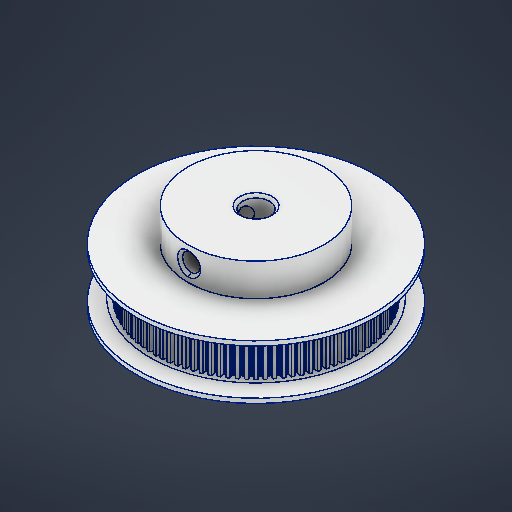
# Autodesk Inventor part: 48 Timing Belt Pulli
Saved by Autodesk Inventor 2026.2 (Build 302298010, 298A)
## iProperties
Created: 2026-04-25
Part Number: 48 Timing Belt Pulli
Material: 알루미늄 6061
Document SubType Name: Modeling
Designer: work
Density: 2.7 g/cm^3
Appearance: 알루미늄 - 평지
Author: work
Autodesk Inventor part; units mm, degrees
ref_plane "XZ Plane" through (0, 0, 0) normal (0, 1, 0) x (-1, 0, 0)
ref_plane "XY Plane" through (0, 0, 0) normal (0, 0, 1) x (1, 0, 0)
sketch "스케치1" plane through (0, 0, 0) normal (0, 1, 0) x (-1, 0, 0)
  circle A0 centre (0, 0) radius 22
  dimension "d0" = 44
  constraints: 1 centre point, 1 coincident
  measures "d0" diameter of A0
extrude "돌출1" add sketch "스케치1" along normal blind 10
sketch "스케치2" plane through (0, 10, 0) normal (0, 1, 0) x (1, 0, 0)
  circle A0 centre (0, 0) radius 12.5
  dimension "d3" = 25
  constraints: 1 centre point, 1 coincident
  measures "d3" diameter of A0
extrude "돌출2" add sketch "스케치2" along normal blind 6
sketch "스케치3" plane through (0, 16, 0) normal (0, 1, 0) x (1, 0, 0)
  circle A0 centre (0, 0) radius 2.5
  dimension "d6" = 5
  constraints: 1 centre point, 1 coincident
  measures "d6" diameter of A0
extrude "돌출3" cut sketch "스케치3" against normal through all
ref_plane "작업 평면1" through (0, 1.5, 0) normal (0, -1, 0) x (1, 0, 0)
sketch "스케치4" plane through (0, 1.5, 0) normal (0, -1, 0) x (1, 0, 0)
  circle A0 centre (0, 0) radius 2.5 projected
  line L0 (0, 0) -> (0, 18.7) construction
  line L1 (0, 18.7) -> (0.2511, 18.7)
  line L2 (0.2511, 18.7) -> (0.3833, 17.95)
  line L3 (0.3833, 17.95) -> (0.6344, 17.95)
  line L4 (0, 18.7) -> (-0.2511, 18.7)
  line L5 (-0.2511, 18.7) -> (-0.3833, 17.95)
  line L6 (-0.3833, 17.95) -> (-0.6344, 17.95)
  circle A1 centre (0, 0) radius 2.5 projected
  circle A2 centre (0, 0) radius 22 projected
  line L7 (0, 0) -> (-1.223, 18.66) construction
  line L8 (-1.223, 18.66) -> (-0.9725, 18.6764)
  line L9 (-0.9725, 18.6764) -> (-0.7915, 17.9366)
  line L10 (-0.7915, 17.9366) -> (-0.541, 17.9531)
  line L11 (-1.223, 18.66) -> (-1.4736, 18.6435)
  line L12 (-1.4736, 18.6435) -> (-1.5565, 17.8865)
  line L13 (-1.5565, 17.8865) -> (-1.807, 17.8701)
  line L14 (0, 0) -> (-2.4408, 18.54) construction
  line L15 (-2.4408, 18.54) -> (-2.1919, 18.5728)
  line L16 (-2.1919, 18.5728) -> (-1.9629, 17.8465)
  line L17 (-1.9629, 17.8465) -> (-1.714, 17.8792)
  line L18 (-2.4408, 18.54) -> (-2.6898, 18.5072)
  line L19 (-2.6898, 18.5072) -> (-2.723, 17.7464)
  line L20 (-2.723, 17.7464) -> (-2.9719, 17.7136)
  line L21 (0, 0) -> (-3.6482, 18.3407) construction
  line L22 (-3.6482, 18.3407) -> (-3.4019, 18.3897)
  line L23 (-3.4019, 18.3897) -> (-3.1259, 17.6799)
  line L24 (-3.1259, 17.6799) -> (-2.8797, 17.7289)
  line L25 (-3.6482, 18.3407) -> (-3.8944, 18.2917)
  line L26 (-3.8944, 18.2917) -> (-3.8778, 17.5303)
  line L27 (-3.8778, 17.5303) -> (-4.1241, 17.4813)
  line L28 (0, 0) -> (-4.8399, 18.0628) construction
  line L29 (-4.8399, 18.0628) -> (-4.5974, 18.1278)
  line L30 (-4.5974, 18.1278) -> (-4.2756, 17.4376)
  line L31 (-4.2756, 17.4376) -> (-4.033, 17.5026)
  line L32 (-4.8399, 18.0628) -> (-5.0824, 17.9978)
  line L33 (-5.0824, 17.9978) -> (-5.0161, 17.2392)
  line L34 (-5.0161, 17.2392) -> (-5.2586, 17.1742)
  line L35 (0, 0) -> (-6.0109, 17.7076) construction
  line L36 (-6.0109, 17.7076) -> (-5.7732, 17.7883)
  line L37 (-5.7732, 17.7883) -> (-5.4069, 17.1206)
  line L38 (-5.4069, 17.1206) -> (-5.1691, 17.2013)
  line L39 (-6.0109, 17.7076) -> (-6.2487, 17.6269)
  line L40 (-6.2487, 17.6269) -> (-6.1328, 16.8742)
  line L41 (-6.1328, 16.8742) -> (-6.3705, 16.7935)
  line L42 (0, 0) -> (-7.1562, 17.2765) construction
  line L43 (-7.1562, 17.2765) -> (-6.9242, 17.3726)
  line L44 (-6.9242, 17.3726) -> (-6.515, 16.7303)
  line L45 (-6.515, 16.7303) -> (-6.2831, 16.8264)
  line L46 (-7.1562, 17.2765) -> (-7.3881, 17.1805)
  line L47 (-7.3881, 17.1805) -> (-7.2233, 16.437)
  line L48 (-7.2233, 16.437) -> (-7.4553, 16.3409)
  line L49 (0, 0) -> (-8.2708, 16.7715) construction
  line L50 (-8.2708, 16.7715) -> (-8.0456, 16.8826)
  line L51 (-8.0456, 16.8826) -> (-7.5953, 16.2684)
  line L52 (-7.5953, 16.2684) -> (-7.3701, 16.3794)
  line L53 (-8.2708, 16.7715) -> (-8.496, 16.6605)
  line L54 (-8.496, 16.6605) -> (-8.2829, 15.9293)
  line L55 (-8.2829, 15.9293) -> (-8.508, 15.8183)
  line L56 (0, 0) -> (-9.35, 16.1947) construction
  line L57 (-9.35, 16.1947) -> (-9.1326, 16.3202)
  line L58 (-9.1326, 16.3202) -> (-8.643, 15.7368)
  line L59 (-8.643, 15.7368) -> (-8.4256, 15.8623)
  line L60 (-9.35, 16.1947) -> (-9.5674, 16.0691)
  line L61 (-9.5674, 16.0691) -> (-9.307, 15.3535)
  line L62 (-9.307, 15.3535) -> (-9.5244, 15.228)
  line L63 (0, 0) -> (-10.3892, 15.5485) construction
  line L64 (-10.3892, 15.5485) -> (-10.1804, 15.688)
  line L65 (-10.1804, 15.688) -> (-9.6538, 15.1378)
  line L66 (-9.6538, 15.1378) -> (-9.445, 15.2773)
  line L67 (-10.3892, 15.5485) -> (-10.5979, 15.409)
  line L68 (-10.5979, 15.409) -> (-10.2912, 14.7119)
  line L69 (-10.2912, 14.7119) -> (-10.4999, 14.5724)
  line L70 (0, 0) -> (-11.3838, 14.8357) construction
  line L71 (-11.3838, 14.8357) -> (-11.1847, 14.9885)
  line L72 (-11.1847, 14.9885) -> (-10.6232, 14.474)
  line L73 (-10.6232, 14.474) -> (-10.424, 14.6269)
  line L74 (-11.3838, 14.8357) -> (-11.583, 14.6829)
  line L75 (-11.583, 14.6829) -> (-11.2314, 14.0073)
  line L76 (-11.2314, 14.0073) -> (-11.4306, 13.8545)
  line L77 (0, 0) -> (-12.3298, 14.0594) construction
  line L78 (-12.3298, 14.0594) -> (-12.141, 14.2249)
  line L79 (-12.141, 14.2249) -> (-11.5471, 13.7483)
  line L80 (-11.5471, 13.7483) -> (-11.3583, 13.9138)
  line L81 (-12.3298, 14.0594) -> (-12.5185, 13.8939)
  line L82 (-12.5185, 13.8939) -> (-12.1234, 13.2428)
  line L83 (-12.1234, 13.2428) -> (-12.3122, 13.0773)
  line L84 (0, 0) -> (-13.2229, 13.2229) construction
  line L85 (-13.2229, 13.2229) -> (-13.0454, 13.4004)
  line L86 (-13.0454, 13.4004) -> (-12.4215, 12.9636)
  line L87 (-12.4215, 12.9636) -> (-12.244, 13.1411)
  line L88 (-13.2229, 13.2229) -> (-13.4004, 13.0454)
  line L89 (-13.4004, 13.0454) -> (-12.9636, 12.4215)
  line L90 (-12.9636, 12.4215) -> (-13.1411, 12.244)
  line L91 (0, 0) -> (-14.0594, 12.3298) construction
  line L92 (-14.0594, 12.3298) -> (-13.8939, 12.5185)
  line L93 (-13.8939, 12.5185) -> (-13.2428, 12.1234)
  line L94 (-13.2428, 12.1234) -> (-13.0773, 12.3122)
  line L95 (-14.0594, 12.3298) -> (-14.2249, 12.141)
  line L96 (-14.2249, 12.141) -> (-13.7483, 11.5471)
  line L97 (-13.7483, 11.5471) -> (-13.9138, 11.3583)
  line L98 (0, 0) -> (-14.8357, 11.3838) construction
  line L99 (-14.8357, 11.3838) -> (-14.6829, 11.583)
  line L100 (-14.6829, 11.583) -> (-14.0073, 11.2314)
  line L101 (-14.0073, 11.2314) -> (-13.8545, 11.4306)
  line L102 (-14.8357, 11.3838) -> (-14.9885, 11.1847)
  line L103 (-14.9885, 11.1847) -> (-14.474, 10.6232)
  line L104 (-14.474, 10.6232) -> (-14.6269, 10.424)
  line L105 (0, 0) -> (-15.5485, 10.3892) construction
  line L106 (-15.5485, 10.3892) -> (-15.409, 10.5979)
  line L107 (-15.409, 10.5979) -> (-14.7119, 10.2912)
  line L108 (-14.7119, 10.2912) -> (-14.5724, 10.4999)
  line L109 (-15.5485, 10.3892) -> (-15.688, 10.1804)
  line L110 (-15.688, 10.1804) -> (-15.1378, 9.6538)
  line L111 (-15.1378, 9.6538) -> (-15.2773, 9.445)
  line L112 (0, 0) -> (-16.1947, 9.35) construction
  line L113 (-16.1947, 9.35) -> (-16.0691, 9.5674)
  line L114 (-16.0691, 9.5674) -> (-15.3535, 9.307)
  line L115 (-15.3535, 9.307) -> (-15.228, 9.5244)
  line L116 (-16.1947, 9.35) -> (-16.3202, 9.1326)
  line L117 (-16.3202, 9.1326) -> (-15.7368, 8.643)
  line L118 (-15.7368, 8.643) -> (-15.8623, 8.4256)
  line L119 (0, 0) -> (-16.7715, 8.2708) construction
  line L120 (-16.7715, 8.2708) -> (-16.6605, 8.496)
  line L121 (-16.6605, 8.496) -> (-15.9293, 8.2829)
  line L122 (-15.9293, 8.2829) -> (-15.8183, 8.508)
  line L123 (-16.7715, 8.2708) -> (-16.8826, 8.0456)
  line L124 (-16.8826, 8.0456) -> (-16.2684, 7.5953)
  line L125 (-16.2684, 7.5953) -> (-16.3794, 7.3701)
  line L126 (0, 0) -> (-17.2765, 7.1562) construction
  line L127 (-17.2765, 7.1562) -> (-17.1805, 7.3881)
  line L128 (-17.1805, 7.3881) -> (-16.437, 7.2233)
  line L129 (-16.437, 7.2233) -> (-16.3409, 7.4553)
  line L130 (-17.2765, 7.1562) -> (-17.3726, 6.9242)
  line L131 (-17.3726, 6.9242) -> (-16.7303, 6.515)
  line L132 (-16.7303, 6.515) -> (-16.8264, 6.2831)
  line L133 (0, 0) -> (-17.7076, 6.0109) construction
  line L134 (-17.7076, 6.0109) -> (-17.6269, 6.2487)
  line L135 (-17.6269, 6.2487) -> (-16.8742, 6.1328)
  line L136 (-16.8742, 6.1328) -> (-16.7935, 6.3705)
  line L137 (-17.7076, 6.0109) -> (-17.7883, 5.7732)
  line L138 (-17.7883, 5.7732) -> (-17.1206, 5.4069)
  line L139 (-17.1206, 5.4069) -> (-17.2013, 5.1691)
  line L140 (0, 0) -> (-18.0628, 4.8399) construction
  line L141 (-18.0628, 4.8399) -> (-17.9978, 5.0824)
  line L142 (-17.9978, 5.0824) -> (-17.2392, 5.0161)
  line L143 (-17.2392, 5.0161) -> (-17.1742, 5.2586)
  line L144 (-18.0628, 4.8399) -> (-18.1278, 4.5974)
  line L145 (-18.1278, 4.5974) -> (-17.4376, 4.2756)
  line L146 (-17.4376, 4.2756) -> (-17.5026, 4.033)
  line L147 (0, 0) -> (-18.3407, 3.6482) construction
  line L148 (-18.3407, 3.6482) -> (-18.2917, 3.8944)
  line L149 (-18.2917, 3.8944) -> (-17.5303, 3.8778)
  line L150 (-17.5303, 3.8778) -> (-17.4813, 4.1241)
  line L151 (-18.3407, 3.6482) -> (-18.3897, 3.4019)
  line L152 (-18.3897, 3.4019) -> (-17.6799, 3.1259)
  line L153 (-17.6799, 3.1259) -> (-17.7289, 2.8797)
  line L154 (0, 0) -> (-18.54, 2.4408) construction
  line L155 (-18.54, 2.4408) -> (-18.5072, 2.6898)
  line L156 (-18.5072, 2.6898) -> (-17.7464, 2.723)
  line L157 (-17.7464, 2.723) -> (-17.7136, 2.9719)
  line L158 (-18.54, 2.4408) -> (-18.5728, 2.1919)
  line L159 (-18.5728, 2.1919) -> (-17.8465, 1.9629)
  line L160 (-17.8465, 1.9629) -> (-17.8792, 1.714)
  line L161 (0, 0) -> (-18.66, 1.223) construction
  line L162 (-18.66, 1.223) -> (-18.6435, 1.4736)
  line L163 (-18.6435, 1.4736) -> (-17.8865, 1.5565)
  line L164 (-17.8865, 1.5565) -> (-17.8701, 1.807)
  line L165 (-18.66, 1.223) -> (-18.6764, 0.9725)
  line L166 (-18.6764, 0.9725) -> (-17.9366, 0.7915)
  line L167 (-17.9366, 0.7915) -> (-17.9531, 0.541)
  line L168 (0, 0) -> (-18.7, 0) construction
  line L169 (-18.7, 0) -> (-18.7, 0.2511)
  line L170 (-18.7, 0.2511) -> (-17.95, 0.3833)
  line L171 (-17.95, 0.3833) -> (-17.95, 0.6344)
  line L172 (-18.7, 0) -> (-18.7, -0.2511)
  line L173 (-18.7, -0.2511) -> (-17.95, -0.3833)
  line L174 (-17.95, -0.3833) -> (-17.95, -0.6344)
  line L175 (0, 0) -> (-18.66, -1.223) construction
  line L176 (-18.66, -1.223) -> (-18.6764, -0.9725)
  line L177 (-18.6764, -0.9725) -> (-17.9366, -0.7915)
  line L178 (-17.9366, -0.7915) -> (-17.9531, -0.541)
  line L179 (-18.66, -1.223) -> (-18.6435, -1.4736)
  line L180 (-18.6435, -1.4736) -> (-17.8865, -1.5565)
  line L181 (-17.8865, -1.5565) -> (-17.8701, -1.807)
  line L182 (0, 0) -> (-18.54, -2.4408) construction
  line L183 (-18.54, -2.4408) -> (-18.5728, -2.1919)
  line L184 (-18.5728, -2.1919) -> (-17.8465, -1.9629)
  line L185 (-17.8465, -1.9629) -> (-17.8792, -1.714)
  line L186 (-18.54, -2.4408) -> (-18.5072, -2.6898)
  line L187 (-18.5072, -2.6898) -> (-17.7464, -2.723)
  line L188 (-17.7464, -2.723) -> (-17.7136, -2.9719)
  line L189 (0, 0) -> (-18.3407, -3.6482) construction
  line L190 (-18.3407, -3.6482) -> (-18.3897, -3.4019)
  line L191 (-18.3897, -3.4019) -> (-17.6799, -3.1259)
  line L192 (-17.6799, -3.1259) -> (-17.7289, -2.8797)
  line L193 (-18.3407, -3.6482) -> (-18.2917, -3.8944)
  line L194 (-18.2917, -3.8944) -> (-17.5303, -3.8778)
  line L195 (-17.5303, -3.8778) -> (-17.4813, -4.1241)
  line L196 (0, 0) -> (-18.0628, -4.8399) construction
  line L197 (-18.0628, -4.8399) -> (-18.1278, -4.5974)
  line L198 (-18.1278, -4.5974) -> (-17.4376, -4.2756)
  line L199 (-17.4376, -4.2756) -> (-17.5026, -4.033)
  line L200 (-18.0628, -4.8399) -> (-17.9978, -5.0824)
  line L201 (-17.9978, -5.0824) -> (-17.2392, -5.0161)
  line L202 (-17.2392, -5.0161) -> (-17.1742, -5.2586)
  line L203 (0, 0) -> (-17.7076, -6.0109) construction
  line L204 (-17.7076, -6.0109) -> (-17.7883, -5.7732)
  line L205 (-17.7883, -5.7732) -> (-17.1206, -5.4069)
  line L206 (-17.1206, -5.4069) -> (-17.2013, -5.1691)
  line L207 (-17.7076, -6.0109) -> (-17.6269, -6.2487)
  line L208 (-17.6269, -6.2487) -> (-16.8742, -6.1328)
  line L209 (-16.8742, -6.1328) -> (-16.7935, -6.3705)
  line L210 (0, 0) -> (-17.2765, -7.1562) construction
  line L211 (-17.2765, -7.1562) -> (-17.3726, -6.9242)
  line L212 (-17.3726, -6.9242) -> (-16.7303, -6.515)
  line L213 (-16.7303, -6.515) -> (-16.8264, -6.2831)
  line L214 (-17.2765, -7.1562) -> (-17.1805, -7.3881)
  line L215 (-17.1805, -7.3881) -> (-16.437, -7.2233)
  line L216 (-16.437, -7.2233) -> (-16.3409, -7.4553)
  line L217 (0, 0) -> (-16.7715, -8.2708) construction
  line L218 (-16.7715, -8.2708) -> (-16.8826, -8.0456)
  line L219 (-16.8826, -8.0456) -> (-16.2684, -7.5953)
  line L220 (-16.2684, -7.5953) -> (-16.3794, -7.3701)
  line L221 (-16.7715, -8.2708) -> (-16.6605, -8.496)
  line L222 (-16.6605, -8.496) -> (-15.9293, -8.2829)
  line L223 (-15.9293, -8.2829) -> (-15.8183, -8.508)
  line L224 (0, 0) -> (-16.1947, -9.35) construction
  line L225 (-16.1947, -9.35) -> (-16.3202, -9.1326)
  line L226 (-16.3202, -9.1326) -> (-15.7368, -8.643)
  line L227 (-15.7368, -8.643) -> (-15.8623, -8.4256)
  line L228 (-16.1947, -9.35) -> (-16.0691, -9.5674)
  line L229 (-16.0691, -9.5674) -> (-15.3535, -9.307)
  line L230 (-15.3535, -9.307) -> (-15.228, -9.5244)
  line L231 (0, 0) -> (-15.5485, -10.3892) construction
  line L232 (-15.5485, -10.3892) -> (-15.688, -10.1804)
  line L233 (-15.688, -10.1804) -> (-15.1378, -9.6538)
  line L234 (-15.1378, -9.6538) -> (-15.2773, -9.445)
  line L235 (-15.5485, -10.3892) -> (-15.409, -10.5979)
  line L236 (-15.409, -10.5979) -> (-14.7119, -10.2912)
  line L237 (-14.7119, -10.2912) -> (-14.5724, -10.4999)
  line L238 (0, 0) -> (-14.8357, -11.3838) construction
  line L239 (-14.8357, -11.3838) -> (-14.9885, -11.1847)
  line L240 (-14.9885, -11.1847) -> (-14.474, -10.6232)
  line L241 (-14.474, -10.6232) -> (-14.6269, -10.424)
  line L242 (-14.8357, -11.3838) -> (-14.6829, -11.583)
  line L243 (-14.6829, -11.583) -> (-14.0073, -11.2314)
  line L244 (-14.0073, -11.2314) -> (-13.8545, -11.4306)
  line L245 (0, 0) -> (-14.0594, -12.3298) construction
  line L246 (-14.0594, -12.3298) -> (-14.2249, -12.141)
  line L247 (-14.2249, -12.141) -> (-13.7483, -11.5471)
  line L248 (-13.7483, -11.5471) -> (-13.9138, -11.3583)
  line L249 (-14.0594, -12.3298) -> (-13.8939, -12.5185)
  line L250 (-13.8939, -12.5185) -> (-13.2428, -12.1234)
  line L251 (-13.2428, -12.1234) -> (-13.0773, -12.3122)
  line L252 (0, 0) -> (-13.2229, -13.2229) construction
  line L253 (-13.2229, -13.2229) -> (-13.4004, -13.0454)
  line L254 (-13.4004, -13.0454) -> (-12.9636, -12.4215)
  line L255 (-12.9636, -12.4215) -> (-13.1411, -12.244)
  line L256 (-13.2229, -13.2229) -> (-13.0454, -13.4004)
  line L257 (-13.0454, -13.4004) -> (-12.4215, -12.9636)
  line L258 (-12.4215, -12.9636) -> (-12.244, -13.1411)
  line L259 (0, 0) -> (-12.3298, -14.0594) construction
  line L260 (-12.3298, -14.0594) -> (-12.5185, -13.8939)
  line L261 (-12.5185, -13.8939) -> (-12.1234, -13.2428)
  line L262 (-12.1234, -13.2428) -> (-12.3122, -13.0773)
  line L263 (-12.3298, -14.0594) -> (-12.141, -14.2249)
  line L264 (-12.141, -14.2249) -> (-11.5471, -13.7483)
  line L265 (-11.5471, -13.7483) -> (-11.3583, -13.9138)
  line L266 (0, 0) -> (-11.3838, -14.8357) construction
  line L267 (-11.3838, -14.8357) -> (-11.583, -14.6829)
  line L268 (-11.583, -14.6829) -> (-11.2314, -14.0073)
  line L269 (-11.2314, -14.0073) -> (-11.4306, -13.8545)
  line L270 (-11.3838, -14.8357) -> (-11.1847, -14.9885)
  line L271 (-11.1847, -14.9885) -> (-10.6232, -14.474)
  line L272 (-10.6232, -14.474) -> (-10.424, -14.6269)
  line L273 (0, 0) -> (-10.3892, -15.5485) construction
  line L274 (-10.3892, -15.5485) -> (-10.5979, -15.409)
  line L275 (-10.5979, -15.409) -> (-10.2912, -14.7119)
  line L276 (-10.2912, -14.7119) -> (-10.4999, -14.5724)
  line L277 (-10.3892, -15.5485) -> (-10.1804, -15.688)
  line L278 (-10.1804, -15.688) -> (-9.6538, -15.1378)
  line L279 (-9.6538, -15.1378) -> (-9.445, -15.2773)
  line L280 (0, 0) -> (-9.35, -16.1947) construction
  line L281 (-9.35, -16.1947) -> (-9.5674, -16.0691)
  line L282 (-9.5674, -16.0691) -> (-9.307, -15.3535)
  line L283 (-9.307, -15.3535) -> (-9.5244, -15.228)
  line L284 (-9.35, -16.1947) -> (-9.1326, -16.3202)
  line L285 (-9.1326, -16.3202) -> (-8.643, -15.7368)
  line L286 (-8.643, -15.7368) -> (-8.4256, -15.8623)
  line L287 (0, 0) -> (-8.2708, -16.7715) construction
  line L288 (-8.2708, -16.7715) -> (-8.496, -16.6605)
  line L289 (-8.496, -16.6605) -> (-8.2829, -15.9293)
  line L290 (-8.2829, -15.9293) -> (-8.508, -15.8183)
  line L291 (-8.2708, -16.7715) -> (-8.0456, -16.8826)
  line L292 (-8.0456, -16.8826) -> (-7.5953, -16.2684)
  line L293 (-7.5953, -16.2684) -> (-7.3701, -16.3794)
  line L294 (0, 0) -> (-7.1562, -17.2765) construction
  line L295 (-7.1562, -17.2765) -> (-7.3881, -17.1805)
  line L296 (-7.3881, -17.1805) -> (-7.2233, -16.437)
  line L297 (-7.2233, -16.437) -> (-7.4553, -16.3409)
  line L298 (-7.1562, -17.2765) -> (-6.9242, -17.3726)
  line L299 (-6.9242, -17.3726) -> (-6.515, -16.7303)
  line L300 (-6.515, -16.7303) -> (-6.2831, -16.8264)
  line L301 (0, 0) -> (-6.0109, -17.7076) construction
  line L302 (-6.0109, -17.7076) -> (-6.2487, -17.6269)
  line L303 (-6.2487, -17.6269) -> (-6.1328, -16.8742)
  line L304 (-6.1328, -16.8742) -> (-6.3705, -16.7935)
  line L305 (-6.0109, -17.7076) -> (-5.7732, -17.7883)
  line L306 (-5.7732, -17.7883) -> (-5.4069, -17.1206)
  line L307 (-5.4069, -17.1206) -> (-5.1691, -17.2013)
  line L308 (0, 0) -> (-4.8399, -18.0628) construction
  line L309 (-4.8399, -18.0628) -> (-5.0824, -17.9978)
  line L310 (-5.0824, -17.9978) -> (-5.0161, -17.2392)
  line L311 (-5.0161, -17.2392) -> (-5.2586, -17.1742)
  line L312 (-4.8399, -18.0628) -> (-4.5974, -18.1278)
  line L313 (-4.5974, -18.1278) -> (-4.2756, -17.4376)
  line L314 (-4.2756, -17.4376) -> (-4.033, -17.5026)
  line L315 (0, 0) -> (-3.6482, -18.3407) construction
  line L316 (-3.6482, -18.3407) -> (-3.8944, -18.2917)
  line L317 (-3.8944, -18.2917) -> (-3.8778, -17.5303)
  line L318 (-3.8778, -17.5303) -> (-4.1241, -17.4813)
  line L319 (-3.6482, -18.3407) -> (-3.4019, -18.3897)
  line L320 (-3.4019, -18.3897) -> (-3.1259, -17.6799)
  line L321 (-3.1259, -17.6799) -> (-2.8797, -17.7289)
  line L322 (0, 0) -> (-2.4408, -18.54) construction
  line L323 (-2.4408, -18.54) -> (-2.6898, -18.5072)
  line L324 (-2.6898, -18.5072) -> (-2.723, -17.7464)
  line L325 (-2.723, -17.7464) -> (-2.9719, -17.7136)
  line L326 (-2.4408, -18.54) -> (-2.1919, -18.5728)
  line L327 (-2.1919, -18.5728) -> (-1.9629, -17.8465)
  line L328 (-1.9629, -17.8465) -> (-1.714, -17.8792)
  line L329 (0, 0) -> (-1.223, -18.66) construction
  line L330 (-1.223, -18.66) -> (-1.4736, -18.6435)
  line L331 (-1.4736, -18.6435) -> (-1.5565, -17.8865)
  line L332 (-1.5565, -17.8865) -> (-1.807, -17.8701)
  line L333 (-1.223, -18.66) -> (-0.9725, -18.6764)
  line L334 (-0.9725, -18.6764) -> (-0.7915, -17.9366)
  line L335 (-0.7915, -17.9366) -> (-0.541, -17.9531)
  line L336 (0, 0) -> (0, -18.7) construction
  line L337 (0, -18.7) -> (-0.2511, -18.7)
  line L338 (-0.2511, -18.7) -> (-0.3833, -17.95)
  line L339 (-0.3833, -17.95) -> (-0.6344, -17.95)
  line L340 (0, -18.7) -> (0.2511, -18.7)
  line L341 (0.2511, -18.7) -> (0.3833, -17.95)
  line L342 (0.3833, -17.95) -> (0.6344, -17.95)
  line L343 (0, 0) -> (1.223, -18.66) construction
  line L344 (1.223, -18.66) -> (0.9725, -18.6764)
  line L345 (0.9725, -18.6764) -> (0.7915, -17.9366)
  line L346 (0.7915, -17.9366) -> (0.541, -17.9531)
  line L347 (1.223, -18.66) -> (1.4736, -18.6435)
  line L348 (1.4736, -18.6435) -> (1.5565, -17.8865)
  line L349 (1.5565, -17.8865) -> (1.807, -17.8701)
  line L350 (0, 0) -> (2.4408, -18.54) construction
  line L351 (2.4408, -18.54) -> (2.1919, -18.5728)
  line L352 (2.1919, -18.5728) -> (1.9629, -17.8465)
  line L353 (1.9629, -17.8465) -> (1.714, -17.8792)
  line L354 (2.4408, -18.54) -> (2.6898, -18.5072)
  line L355 (2.6898, -18.5072) -> (2.723, -17.7464)
  line L356 (2.723, -17.7464) -> (2.9719, -17.7136)
  line L357 (0, 0) -> (3.6482, -18.3407) construction
  line L358 (3.6482, -18.3407) -> (3.4019, -18.3897)
  line L359 (3.4019, -18.3897) -> (3.1259, -17.6799)
  line L360 (3.1259, -17.6799) -> (2.8797, -17.7289)
  line L361 (3.6482, -18.3407) -> (3.8944, -18.2917)
  line L362 (3.8944, -18.2917) -> (3.8778, -17.5303)
  line L363 (3.8778, -17.5303) -> (4.1241, -17.4813)
  line L364 (0, 0) -> (4.8399, -18.0628) construction
  line L365 (4.8399, -18.0628) -> (4.5974, -18.1278)
  line L366 (4.5974, -18.1278) -> (4.2756, -17.4376)
  line L367 (4.2756, -17.4376) -> (4.033, -17.5026)
  line L368 (4.8399, -18.0628) -> (5.0824, -17.9978)
  line L369 (5.0824, -17.9978) -> (5.0161, -17.2392)
  line L370 (5.0161, -17.2392) -> (5.2586, -17.1742)
  line L371 (0, 0) -> (6.0109, -17.7076) construction
  line L372 (6.0109, -17.7076) -> (5.7732, -17.7883)
  line L373 (5.7732, -17.7883) -> (5.4069, -17.1206)
  line L374 (5.4069, -17.1206) -> (5.1691, -17.2013)
  line L375 (6.0109, -17.7076) -> (6.2487, -17.6269)
  line L376 (6.2487, -17.6269) -> (6.1328, -16.8742)
  line L377 (6.1328, -16.8742) -> (6.3705, -16.7935)
  line L378 (0, 0) -> (7.1562, -17.2765) construction
  line L379 (7.1562, -17.2765) -> (6.9242, -17.3726)
  line L380 (6.9242, -17.3726) -> (6.515, -16.7303)
  line L381 (6.515, -16.7303) -> (6.2831, -16.8264)
  line L382 (7.1562, -17.2765) -> (7.3881, -17.1805)
  line L383 (7.3881, -17.1805) -> (7.2233, -16.437)
  line L384 (7.2233, -16.437) -> (7.4553, -16.3409)
  line L385 (0, 0) -> (8.2708, -16.7715) construction
  line L386 (8.2708, -16.7715) -> (8.0456, -16.8826)
  line L387 (8.0456, -16.8826) -> (7.5953, -16.2684)
  line L388 (7.5953, -16.2684) -> (7.3701, -16.3794)
  line L389 (8.2708, -16.7715) -> (8.496, -16.6605)
  line L390 (8.496, -16.6605) -> (8.2829, -15.9293)
  line L391 (8.2829, -15.9293) -> (8.508, -15.8183)
  line L392 (0, 0) -> (9.35, -16.1947) construction
  line L393 (9.35, -16.1947) -> (9.1326, -16.3202)
  line L394 (9.1326, -16.3202) -> (8.643, -15.7368)
  line L395 (8.643, -15.7368) -> (8.4256, -15.8623)
  line L396 (9.35, -16.1947) -> (9.5674, -16.0691)
  line L397 (9.5674, -16.0691) -> (9.307, -15.3535)
  line L398 (9.307, -15.3535) -> (9.5244, -15.228)
  line L399 (0, 0) -> (10.3892, -15.5485) construction
  line L400 (10.3892, -15.5485) -> (10.1804, -15.688)
  line L401 (10.1804, -15.688) -> (9.6538, -15.1378)
  line L402 (9.6538, -15.1378) -> (9.445, -15.2773)
  line L403 (10.3892, -15.5485) -> (10.5979, -15.409)
  line L404 (10.5979, -15.409) -> (10.2912, -14.7119)
  line L405 (10.2912, -14.7119) -> (10.4999, -14.5724)
  line L406 (0, 0) -> (11.3838, -14.8357) construction
  line L407 (11.3838, -14.8357) -> (11.1847, -14.9885)
  line L408 (11.1847, -14.9885) -> (10.6232, -14.474)
  line L409 (10.6232, -14.474) -> (10.424, -14.6269)
  line L410 (11.3838, -14.8357) -> (11.583, -14.6829)
  line L411 (11.583, -14.6829) -> (11.2314, -14.0073)
  line L412 (11.2314, -14.0073) -> (11.4306, -13.8545)
  line L413 (0, 0) -> (12.3298, -14.0594) construction
  line L414 (12.3298, -14.0594) -> (12.141, -14.2249)
  line L415 (12.141, -14.2249) -> (11.5471, -13.7483)
  line L416 (11.5471, -13.7483) -> (11.3583, -13.9138)
  line L417 (12.3298, -14.0594) -> (12.5185, -13.8939)
  line L418 (12.5185, -13.8939) -> (12.1234, -13.2428)
  line L419 (12.1234, -13.2428) -> (12.3122, -13.0773)
  line L420 (0, 0) -> (13.2229, -13.2229) construction
  line L421 (13.2229, -13.2229) -> (13.0454, -13.4004)
  line L422 (13.0454, -13.4004) -> (12.4215, -12.9636)
  line L423 (12.4215, -12.9636) -> (12.244, -13.1411)
  line L424 (13.2229, -13.2229) -> (13.4004, -13.0454)
  line L425 (13.4004, -13.0454) -> (12.9636, -12.4215)
  line L426 (12.9636, -12.4215) -> (13.1411, -12.244)
  line L427 (0, 0) -> (14.0594, -12.3298) construction
  line L428 (14.0594, -12.3298) -> (13.8939, -12.5185)
  line L429 (13.8939, -12.5185) -> (13.2428, -12.1234)
  line L430 (13.2428, -12.1234) -> (13.0773, -12.3122)
  line L431 (14.0594, -12.3298) -> (14.2249, -12.141)
  line L432 (14.2249, -12.141) -> (13.7483, -11.5471)
  line L433 (13.7483, -11.5471) -> (13.9138, -11.3583)
  line L434 (0, 0) -> (14.8357, -11.3838) construction
  line L435 (14.8357, -11.3838) -> (14.6829, -11.583)
  line L436 (14.6829, -11.583) -> (14.0073, -11.2314)
  line L437 (14.0073, -11.2314) -> (13.8545, -11.4306)
  line L438 (14.8357, -11.3838) -> (14.9885, -11.1847)
  line L439 (14.9885, -11.1847) -> (14.474, -10.6232)
  line L440 (14.474, -10.6232) -> (14.6269, -10.424)
  line L441 (0, 0) -> (15.5485, -10.3892) construction
  line L442 (15.5485, -10.3892) -> (15.409, -10.5979)
  line L443 (15.409, -10.5979) -> (14.7119, -10.2912)
  line L444 (14.7119, -10.2912) -> (14.5724, -10.4999)
  line L445 (15.5485, -10.3892) -> (15.688, -10.1804)
  line L446 (15.688, -10.1804) -> (15.1378, -9.6538)
  line L447 (15.1378, -9.6538) -> (15.2773, -9.445)
  line L448 (0, 0) -> (16.1947, -9.35) construction
  line L449 (16.1947, -9.35) -> (16.0691, -9.5674)
  line L450 (16.0691, -9.5674) -> (15.3535, -9.307)
  line L451 (15.3535, -9.307) -> (15.228, -9.5244)
  line L452 (16.1947, -9.35) -> (16.3202, -9.1326)
  line L453 (16.3202, -9.1326) -> (15.7368, -8.643)
  line L454 (15.7368, -8.643) -> (15.8623, -8.4256)
  line L455 (0, 0) -> (16.7715, -8.2708) construction
  line L456 (16.7715, -8.2708) -> (16.6605, -8.496)
  line L457 (16.6605, -8.496) -> (15.9293, -8.2829)
  line L458 (15.9293, -8.2829) -> (15.8183, -8.508)
  line L459 (16.7715, -8.2708) -> (16.8826, -8.0456)
  line L460 (16.8826, -8.0456) -> (16.2684, -7.5953)
  line L461 (16.2684, -7.5953) -> (16.3794, -7.3701)
  line L462 (0, 0) -> (17.2765, -7.1562) construction
  line L463 (17.2765, -7.1562) -> (17.1805, -7.3881)
  line L464 (17.1805, -7.3881) -> (16.437, -7.2233)
  line L465 (16.437, -7.2233) -> (16.3409, -7.4553)
  line L466 (17.2765, -7.1562) -> (17.3726, -6.9242)
  line L467 (17.3726, -6.9242) -> (16.7303, -6.515)
  line L468 (16.7303, -6.515) -> (16.8264, -6.2831)
  line L469 (0, 0) -> (17.7076, -6.0109) construction
  line L470 (17.7076, -6.0109) -> (17.6269, -6.2487)
  line L471 (17.6269, -6.2487) -> (16.8742, -6.1328)
  line L472 (16.8742, -6.1328) -> (16.7935, -6.3705)
  line L473 (17.7076, -6.0109) -> (17.7883, -5.7732)
  line L474 (17.7883, -5.7732) -> (17.1206, -5.4069)
  line L475 (17.1206, -5.4069) -> (17.2013, -5.1691)
  line L476 (0, 0) -> (18.0628, -4.8399) construction
  line L477 (18.0628, -4.8399) -> (17.9978, -5.0824)
  line L478 (17.9978, -5.0824) -> (17.2392, -5.0161)
  line L479 (17.2392, -5.0161) -> (17.1742, -5.2586)
  line L480 (18.0628, -4.8399) -> (18.1278, -4.5974)
  line L481 (18.1278, -4.5974) -> (17.4376, -4.2756)
  line L482 (17.4376, -4.2756) -> (17.5026, -4.033)
  line L483 (0, 0) -> (18.3407, -3.6482) construction
  line L484 (18.3407, -3.6482) -> (18.2917, -3.8944)
  line L485 (18.2917, -3.8944) -> (17.5303, -3.8778)
  line L486 (17.5303, -3.8778) -> (17.4813, -4.1241)
  line L487 (18.3407, -3.6482) -> (18.3897, -3.4019)
  line L488 (18.3897, -3.4019) -> (17.6799, -3.1259)
  line L489 (17.6799, -3.1259) -> (17.7289, -2.8797)
  line L490 (0, 0) -> (18.54, -2.4408) construction
  line L491 (18.54, -2.4408) -> (18.5072, -2.6898)
  line L492 (18.5072, -2.6898) -> (17.7464, -2.723)
  line L493 (17.7464, -2.723) -> (17.7136, -2.9719)
  line L494 (18.54, -2.4408) -> (18.5728, -2.1919)
  line L495 (18.5728, -2.1919) -> (17.8465, -1.9629)
  line L496 (17.8465, -1.9629) -> (17.8792, -1.714)
  line L497 (0, 0) -> (18.66, -1.223) construction
  line L498 (18.66, -1.223) -> (18.6435, -1.4736)
  line L499 (18.6435, -1.4736) -> (17.8865, -1.5565)
  line L500 (17.8865, -1.5565) -> (17.8701, -1.807)
  line L501 (18.66, -1.223) -> (18.6764, -0.9725)
  line L502 (18.6764, -0.9725) -> (17.9366, -0.7915)
  line L503 (17.9366, -0.7915) -> (17.9531, -0.541)
  line L504 (0, 0) -> (18.7, 0) construction
  line L505 (18.7, 0) -> (18.7, -0.2511)
  line L506 (18.7, -0.2511) -> (17.95, -0.3833)
  line L507 (17.95, -0.3833) -> (17.95, -0.6344)
  line L508 (18.7, 0) -> (18.7, 0.2511)
  line L509 (18.7, 0.2511) -> (17.95, 0.3833)
  line L510 (17.95, 0.3833) -> (17.95, 0.6344)
  line L511 (0, 0) -> (18.66, 1.223) construction
  line L512 (18.66, 1.223) -> (18.6764, 0.9725)
  line L513 (18.6764, 0.9725) -> (17.9366, 0.7915)
  line L514 (17.9366, 0.7915) -> (17.9531, 0.541)
  line L515 (18.66, 1.223) -> (18.6435, 1.4736)
  line L516 (18.6435, 1.4736) -> (17.8865, 1.5565)
  line L517 (17.8865, 1.5565) -> (17.8701, 1.807)
  line L518 (0, 0) -> (18.54, 2.4408) construction
  line L519 (18.54, 2.4408) -> (18.5728, 2.1919)
  line L520 (18.5728, 2.1919) -> (17.8465, 1.9629)
  line L521 (17.8465, 1.9629) -> (17.8792, 1.714)
  line L522 (18.54, 2.4408) -> (18.5072, 2.6898)
  line L523 (18.5072, 2.6898) -> (17.7464, 2.723)
  line L524 (17.7464, 2.723) -> (17.7136, 2.9719)
  line L525 (0, 0) -> (18.3407, 3.6482) construction
  line L526 (18.3407, 3.6482) -> (18.3897, 3.4019)
  line L527 (18.3897, 3.4019) -> (17.6799, 3.1259)
  line L528 (17.6799, 3.1259) -> (17.7289, 2.8797)
  line L529 (18.3407, 3.6482) -> (18.2917, 3.8944)
  line L530 (18.2917, 3.8944) -> (17.5303, 3.8778)
  line L531 (17.5303, 3.8778) -> (17.4813, 4.1241)
  line L532 (0, 0) -> (18.0628, 4.8399) construction
  line L533 (18.0628, 4.8399) -> (18.1278, 4.5974)
  line L534 (18.1278, 4.5974) -> (17.4376, 4.2756)
  line L535 (17.4376, 4.2756) -> (17.5026, 4.033)
  line L536 (18.0628, 4.8399) -> (17.9978, 5.0824)
  line L537 (17.9978, 5.0824) -> (17.2392, 5.0161)
  line L538 (17.2392, 5.0161) -> (17.1742, 5.2586)
  line L539 (0, 0) -> (17.7076, 6.0109) construction
  line L540 (17.7076, 6.0109) -> (17.7883, 5.7732)
  line L541 (17.7883, 5.7732) -> (17.1206, 5.4069)
  line L542 (17.1206, 5.4069) -> (17.2013, 5.1691)
  line L543 (17.7076, 6.0109) -> (17.6269, 6.2487)
  line L544 (17.6269, 6.2487) -> (16.8742, 6.1328)
  line L545 (16.8742, 6.1328) -> (16.7935, 6.3705)
  line L546 (0, 0) -> (17.2765, 7.1562) construction
  line L547 (17.2765, 7.1562) -> (17.3726, 6.9242)
  line L548 (17.3726, 6.9242) -> (16.7303, 6.515)
  line L549 (16.7303, 6.515) -> (16.8264, 6.2831)
  line L550 (17.2765, 7.1562) -> (17.1805, 7.3881)
  line L551 (17.1805, 7.3881) -> (16.437, 7.2233)
  line L552 (16.437, 7.2233) -> (16.3409, 7.4553)
  line L553 (0, 0) -> (16.7715, 8.2708) construction
  line L554 (16.7715, 8.2708) -> (16.8826, 8.0456)
  line L555 (16.8826, 8.0456) -> (16.2684, 7.5953)
  line L556 (16.2684, 7.5953) -> (16.3794, 7.3701)
  line L557 (16.7715, 8.2708) -> (16.6605, 8.496)
  line L558 (16.6605, 8.496) -> (15.9293, 8.2829)
  line L559 (15.9293, 8.2829) -> (15.8183, 8.508)
  line L560 (0, 0) -> (16.1947, 9.35) construction
  line L561 (16.1947, 9.35) -> (16.3202, 9.1326)
  line L562 (16.3202, 9.1326) -> (15.7368, 8.643)
  line L563 (15.7368, 8.643) -> (15.8623, 8.4256)
  line L564 (16.1947, 9.35) -> (16.0691, 9.5674)
  line L565 (16.0691, 9.5674) -> (15.3535, 9.307)
  line L566 (15.3535, 9.307) -> (15.228, 9.5244)
  line L567 (0, 0) -> (15.5485, 10.3892) construction
  line L568 (15.5485, 10.3892) -> (15.688, 10.1804)
  line L569 (15.688, 10.1804) -> (15.1378, 9.6538)
  line L570 (15.1378, 9.6538) -> (15.2773, 9.445)
  line L571 (15.5485, 10.3892) -> (15.409, 10.5979)
  line L572 (15.409, 10.5979) -> (14.7119, 10.2912)
  line L573 (14.7119, 10.2912) -> (14.5724, 10.4999)
  line L574 (0, 0) -> (14.8357, 11.3838) construction
  line L575 (14.8357, 11.3838) -> (14.9885, 11.1847)
  line L576 (14.9885, 11.1847) -> (14.474, 10.6232)
  line L577 (14.474, 10.6232) -> (14.6269, 10.424)
  line L578 (14.8357, 11.3838) -> (14.6829, 11.583)
  line L579 (14.6829, 11.583) -> (14.0073, 11.2314)
  line L580 (14.0073, 11.2314) -> (13.8545, 11.4306)
  line L581 (0, 0) -> (14.0594, 12.3298) construction
  line L582 (14.0594, 12.3298) -> (14.2249, 12.141)
  line L583 (14.2249, 12.141) -> (13.7483, 11.5471)
  line L584 (13.7483, 11.5471) -> (13.9138, 11.3583)
  line L585 (14.0594, 12.3298) -> (13.8939, 12.5185)
  line L586 (13.8939, 12.5185) -> (13.2428, 12.1234)
  line L587 (13.2428, 12.1234) -> (13.0773, 12.3122)
  line L588 (0, 0) -> (13.2229, 13.2229) construction
  line L589 (13.2229, 13.2229) -> (13.4004, 13.0454)
  line L590 (13.4004, 13.0454) -> (12.9636, 12.4215)
  line L591 (12.9636, 12.4215) -> (13.1411, 12.244)
  line L592 (13.2229, 13.2229) -> (13.0454, 13.4004)
  line L593 (13.0454, 13.4004) -> (12.4215, 12.9636)
  line L594 (12.4215, 12.9636) -> (12.244, 13.1411)
  line L595 (0, 0) -> (12.3298, 14.0594) construction
  line L596 (12.3298, 14.0594) -> (12.5185, 13.8939)
  line L597 (12.5185, 13.8939) -> (12.1234, 13.2428)
  line L598 (12.1234, 13.2428) -> (12.3122, 13.0773)
  line L599 (12.3298, 14.0594) -> (12.141, 14.2249)
  line L600 (12.141, 14.2249) -> (11.5471, 13.7483)
  line L601 (11.5471, 13.7483) -> (11.3583, 13.9138)
  line L602 (0, 0) -> (11.3838, 14.8357) construction
  line L603 (11.3838, 14.8357) -> (11.583, 14.6829)
  line L604 (11.583, 14.6829) -> (11.2314, 14.0073)
  line L605 (11.2314, 14.0073) -> (11.4306, 13.8545)
  line L606 (11.3838, 14.8357) -> (11.1847, 14.9885)
  line L607 (11.1847, 14.9885) -> (10.6232, 14.474)
  line L608 (10.6232, 14.474) -> (10.424, 14.6269)
  line L609 (0, 0) -> (10.3892, 15.5485) construction
  line L610 (10.3892, 15.5485) -> (10.5979, 15.409)
  line L611 (10.5979, 15.409) -> (10.2912, 14.7119)
  line L612 (10.2912, 14.7119) -> (10.4999, 14.5724)
  line L613 (10.3892, 15.5485) -> (10.1804, 15.688)
  line L614 (10.1804, 15.688) -> (9.6538, 15.1378)
  line L615 (9.6538, 15.1378) -> (9.445, 15.2773)
  line L616 (0, 0) -> (9.35, 16.1947) construction
  line L617 (9.35, 16.1947) -> (9.5674, 16.0691)
  line L618 (9.5674, 16.0691) -> (9.307, 15.3535)
  line L619 (9.307, 15.3535) -> (9.5244, 15.228)
  line L620 (9.35, 16.1947) -> (9.1326, 16.3202)
  line L621 (9.1326, 16.3202) -> (8.643, 15.7368)
  line L622 (8.643, 15.7368) -> (8.4256, 15.8623)
  line L623 (0, 0) -> (8.2708, 16.7715) construction
  line L624 (8.2708, 16.7715) -> (8.496, 16.6605)
  line L625 (8.496, 16.6605) -> (8.2829, 15.9293)
  line L626 (8.2829, 15.9293) -> (8.508, 15.8183)
  line L627 (8.2708, 16.7715) -> (8.0456, 16.8826)
  line L628 (8.0456, 16.8826) -> (7.5953, 16.2684)
  line L629 (7.5953, 16.2684) -> (7.3701, 16.3794)
  line L630 (0, 0) -> (7.1562, 17.2765) construction
  line L631 (7.1562, 17.2765) -> (7.3881, 17.1805)
  line L632 (7.3881, 17.1805) -> (7.2233, 16.437)
  line L633 (7.2233, 16.437) -> (7.4553, 16.3409)
  line L634 (7.1562, 17.2765) -> (6.9242, 17.3726)
  line L635 (6.9242, 17.3726) -> (6.515, 16.7303)
  line L636 (6.515, 16.7303) -> (6.2831, 16.8264)
  line L637 (0, 0) -> (6.0109, 17.7076) construction
  line L638 (6.0109, 17.7076) -> (6.2487, 17.6269)
  line L639 (6.2487, 17.6269) -> (6.1328, 16.8742)
  line L640 (6.1328, 16.8742) -> (6.3705, 16.7935)
  line L641 (6.0109, 17.7076) -> (5.7732, 17.7883)
  line L642 (5.7732, 17.7883) -> (5.4069, 17.1206)
  line L643 (5.4069, 17.1206) -> (5.1691, 17.2013)
  line L644 (0, 0) -> (4.8399, 18.0628) construction
  line L645 (4.8399, 18.0628) -> (5.0824, 17.9978)
  line L646 (5.0824, 17.9978) -> (5.0161, 17.2392)
  line L647 (5.0161, 17.2392) -> (5.2586, 17.1742)
  line L648 (4.8399, 18.0628) -> (4.5974, 18.1278)
  line L649 (4.5974, 18.1278) -> (4.2756, 17.4376)
  line L650 (4.2756, 17.4376) -> (4.033, 17.5026)
  line L651 (0, 0) -> (3.6482, 18.3407) construction
  line L652 (3.6482, 18.3407) -> (3.8944, 18.2917)
  line L653 (3.8944, 18.2917) -> (3.8778, 17.5303)
  line L654 (3.8778, 17.5303) -> (4.1241, 17.4813)
  line L655 (3.6482, 18.3407) -> (3.4019, 18.3897)
  line L656 (3.4019, 18.3897) -> (3.1259, 17.6799)
  line L657 (3.1259, 17.6799) -> (2.8797, 17.7289)
  line L658 (0, 0) -> (2.4408, 18.54) construction
  line L659 (2.4408, 18.54) -> (2.6898, 18.5072)
  line L660 (2.6898, 18.5072) -> (2.723, 17.7464)
  line L661 (2.723, 17.7464) -> (2.9719, 17.7136)
  line L662 (2.4408, 18.54) -> (2.1919, 18.5728)
  line L663 (2.1919, 18.5728) -> (1.9629, 17.8465)
  line L664 (1.9629, 17.8465) -> (1.714, 17.8792)
  line L665 (0, 0) -> (1.223, 18.66) construction
  line L666 (1.223, 18.66) -> (1.4736, 18.6435)
  line L667 (1.4736, 18.6435) -> (1.5565, 17.8865)
  line L668 (1.5565, 17.8865) -> (1.807, 17.8701)
  line L669 (1.223, 18.66) -> (0.9725, 18.6764)
  line L670 (0.9725, 18.6764) -> (0.7915, 17.9366)
  line L671 (0.7915, 17.9366) -> (0.541, 17.9531)
  point P0 (0.5876, 17.95)
  point P1 (1.7604, 17.8731)
  point P2 (2.9255, 17.7197)
  point P3 (4.0782, 17.4905)
  point P4 (5.2134, 17.1863)
  point P5 (6.3263, 16.8085)
  point P6 (7.4121, 16.3588)
  point P7 (8.4661, 15.839)
  point P8 (9.4839, 15.2513)
  point P9 (10.4611, 14.5984)
  point P10 (11.3935, 13.883)
  point P11 (12.2771, 13.1081)
  point P12 (13.1081, 12.2771)
  point P13 (13.883, 11.3935)
  point P14 (14.5984, 10.4611)
  point P15 (15.2513, 9.4839)
  point P16 (15.839, 8.4661)
  point P17 (16.3588, 7.4121)
  point P18 (16.8085, 6.3263)
  point P19 (17.1863, 5.2134)
  point P20 (17.4905, 4.0782)
  point P21 (17.7197, 2.9255)
  point P22 (17.8731, 1.7604)
  point P23 (17.95, 0.5876)
  point P24 (17.95, -0.5876)
  point P25 (17.8731, -1.7604)
  point P26 (17.7197, -2.9255)
  point P27 (17.4905, -4.0782)
  point P28 (17.1863, -5.2134)
  point P29 (16.8085, -6.3263)
  point P30 (16.3588, -7.4121)
  point P31 (15.839, -8.4661)
  point P32 (15.2513, -9.4839)
  point P33 (14.5984, -10.4611)
  point P34 (13.883, -11.3935)
  point P35 (13.1081, -12.2771)
  point P36 (12.2771, -13.1081)
  point P37 (11.3935, -13.883)
  point P38 (10.4611, -14.5984)
  point P39 (9.4839, -15.2513)
  point P40 (8.4661, -15.839)
  point P41 (7.4121, -16.3588)
  point P42 (6.3263, -16.8085)
  point P43 (5.2134, -17.1863)
  point P44 (4.0782, -17.4905)
  point P45 (2.9255, -17.7197)
  point P46 (1.7604, -17.8731)
  point P47 (0.5876, -17.95)
  point P48 (-0.5876, -17.95)
  point P49 (-1.7604, -17.8731)
  point P50 (-2.9255, -17.7197)
  point P51 (-4.0782, -17.4905)
  point P52 (-5.2134, -17.1863)
  point P53 (-6.3263, -16.8085)
  point P54 (-7.4121, -16.3588)
  point P55 (-8.4661, -15.839)
  point P56 (-9.4839, -15.2513)
  point P57 (-10.4611, -14.5984)
  point P58 (-11.3935, -13.883)
  point P59 (-12.2771, -13.1081)
  point P60 (-13.1081, -12.2771)
  point P61 (-13.883, -11.3935)
  point P62 (-14.5984, -10.4611)
  point P63 (-15.2513, -9.4839)
  point P64 (-15.839, -8.4661)
  point P65 (-16.3588, -7.4121)
  point P66 (-16.8085, -6.3263)
  point P67 (-17.1863, -5.2134)
  point P68 (-17.4905, -4.0782)
  point P69 (-17.7197, -2.9255)
  point P70 (-17.8731, -1.7604)
  point P71 (-17.95, -0.5876)
  point P72 (-17.95, 0.5876)
  point P73 (-17.8731, 1.7604)
  point P74 (-17.7197, 2.9255)
  point P75 (-17.4905, 4.0782)
  point P76 (-17.1863, 5.2134)
  point P77 (-16.8085, 6.3263)
  point P78 (-16.3588, 7.4121)
  point P79 (-15.839, 8.4661)
  point P80 (-15.2513, 9.4839)
  point P81 (-14.5984, 10.4611)
  point P82 (-13.883, 11.3935)
  point P83 (-13.1081, 12.2771)
  point P84 (-12.2771, 13.1081)
  point P85 (-11.3935, 13.883)
  point P86 (-10.4611, 14.5984)
  point P87 (-9.4839, 15.2513)
  point P88 (-8.4661, 15.839)
  point P89 (-7.4121, 16.3588)
  point P90 (-6.3263, 16.8085)
  point P91 (-5.2134, 17.1863)
  point P92 (-4.0782, 17.4905)
  point P93 (-2.9255, 17.7197)
  point P94 (-1.7604, 17.8731)
  point P95 (-0.5876, 17.95)
  dimension "d10" = 18.7
  dimension "d11" = 0.6344
  dimension "d12" = 100
  dimension "d13" = 0.75
  dimension "d16" = 360
  constraints: 1344 end point, 3 symmetric about line, 2 coincident, 2 parallel, 1 horizontal, 1 vertical, 1439 other
  measures "d10" distance of L0.start L0.end
  measures "d11" horizontal distance of L0.end L3.end
  measures "d12" angle of L1 L2
  measures "d13" vertical distance of L1.end L2.end
extrude "돌출4" cut sketch "스케치4" against normal blind 7 contours A2
chamfer "모따기1" distance 2.5 angle 15 1 edges at (22, 1.5, 0) measured on face at (21.5, 1.5, 0)
chamfer "모따기2" distance 2.5 angle 15 1 edges at (22, 8.5, 0) measured on face at (21.5, 8.5, 0)
ref_plane "작업 평면2" through (-12.5, 10, 0) normal (1, 0, 0) x (0, 1, 0)
sketch "스케치5" plane through (-12.5, 10, 0) normal (1, 0, 0) x (0, 1, 0)
  line L0 (6, -12.5) -> (6, 12.5) projected
  line L1 (6, 0) -> (0, 0) construction
  line L2 (0, -22) -> (0, 22) projected
  point P0 (-10, 0)
  point P1 (3, 0)
  constraints: 3 midpoint, 2 end point, 1 horizontal
hole "구멍1" at (-12.5, 13, 0) direction (1, 0, 0) diameter 3.242 end up to surface thread size "M4x0.7" class "6H" standard "ISO Metric profile"
pattern_circular "원형 패턴1" count 4 over 360 about axis through (0, -10, 0) along (0, 1, 0) of "구멍1" skipped copies 3 4
chamfer "모따기3" distance 0.5 angle 45 7 edges at (-2.5, 16, 0) (-2.5, 0, 0) (1.6139, 13.1515, 12.3954) (-1.621, 13.0008, 12.3944) (-12.4405, 11.9311, 1.2186) (-12.44, 14.0639, 1.223) (-12.3944, 12.9984, -1.621)
